Autodesk Fusion 360 part; units mm, degrees
(part 22 of 28)
  line L283 (90.6748, 11.0958, -1.4859) -> (90.5767, 11.092, -1.4859)
  line L284 (90.5767, 11.092, -1.4859) -> (90.0767, 11.092, -1.4859)
  line L285 (90.0767, 11.092, -1.4859) -> (89.9787, 11.0958, -1.4859)
  line L286 (89.9787, 11.0958, -1.4859) -> (89.7849, 11.1265, -1.4859)
  line L287 (89.7849, 11.1265, -1.4859) -> (89.5984, 11.1871, -1.4859)
  line L288 (89.5984, 11.1871, -1.4859) -> (89.4236, 11.2762, -1.4859)
  line L289 (89.4236, 11.2762, -1.4859) -> (89.2649, 11.3915, -1.4859)
  line L290 (89.2649, 11.3915, -1.4859) -> (89.1262, 11.5301, -1.4859)
  line L291 (89.1262, 11.5301, -1.4859) -> (89.0109, 11.6888, -1.4859)
  line L292 (89.0109, 11.6888, -1.4859) -> (88.9219, 11.8636, -1.4859)
  line L293 (88.9219, 11.8636, -1.4859) -> (88.8613, 12.0501, -1.4859)
  line L294 (88.8613, 12.0501, -1.4859) -> (88.8306, 12.2439, -1.4859)
  line L295 (88.8306, 12.2439, -1.4859) -> (88.8306, 12.44, -1.4859)
  line L296 (88.8306, 12.44, -1.4859) -> (88.8613, 12.6338, -1.4859)
  line L297 (88.8613, 12.6338, -1.4859) -> (88.9219, 12.8203, -1.4859)
  line L298 (88.9219, 12.8203, -1.4859) -> (89.0109, 12.9951, -1.4859)
  line L299 (89.0109, 12.9951, -1.4859) -> (89.1262, 13.1538, -1.4859)
  line L300 (89.1262, 13.1538, -1.4859) -> (89.2649, 13.2925, -1.4859)
  line L301 (89.2649, 13.2925, -1.4859) -> (89.4236, 13.4078, -1.4859)
  line L302 (89.4236, 13.4078, -1.4859) -> (89.5984, 13.4968, -1.4859)
  line L303 (89.5984, 13.4968, -1.4859) -> (89.7849, 13.5574, -1.4859)
  line L304 (89.7849, 13.5574, -1.4859) -> (89.9787, 13.5881, -1.4859)
  line L305 (89.9787, 13.5881, -1.4859) -> (90.0767, 13.592, -1.4859)
  line L306 (90.0767, 13.592, -1.4859) -> (90.5767, 13.592, -1.4859)
  line L307 (90.5767, 13.592, -1.4859) -> (90.6748, 13.5881, -1.4859)
  line L308 (98.2948, 13.5881, -1.4859) -> (98.4885, 13.5574, -1.4859)
  line L309 (98.4885, 13.5574, -1.4859) -> (98.6751, 13.4968, -1.4859)
  line L310 (98.6751, 13.4968, -1.4859) -> (98.8499, 13.4078, -1.4859)
  line L311 (98.8499, 13.4078, -1.4859) -> (99.0085, 13.2925, -1.4859)
  line L312 (99.0085, 13.2925, -1.4859) -> (99.1472, 13.1538, -1.4859)
  line L313 (99.1472, 13.1538, -1.4859) -> (99.2625, 12.9951, -1.4859)
  line L314 (99.2625, 12.9951, -1.4859) -> (99.3516, 12.8203, -1.4859)
  line L315 (99.3516, 12.8203, -1.4859) -> (99.4122, 12.6338, -1.4859)
  line L316 (99.4122, 12.6338, -1.4859) -> (99.4429, 12.44, -1.4859)
  line L317 (99.4429, 12.44, -1.4859) -> (99.4429, 12.2439, -1.4859)
  line L318 (99.4429, 12.2439, -1.4859) -> (99.4122, 12.0501, -1.4859)
  line L319 (99.4122, 12.0501, -1.4859) -> (99.3516, 11.8636, -1.4859)
  line L320 (99.3516, 11.8636, -1.4859) -> (99.2625, 11.6888, -1.4859)
  line L321 (99.2625, 11.6888, -1.4859) -> (99.1472, 11.5301, -1.4859)
  line L322 (99.1472, 11.5301, -1.4859) -> (99.0086, 11.3914, -1.4859)
  line L323 (99.0086, 11.3914, -1.4859) -> (98.8499, 11.2762, -1.4859)
  line L324 (98.8499, 11.2762, -1.4859) -> (98.6751, 11.1871, -1.4859)
  line L325 (98.6751, 11.1871, -1.4859) -> (98.4885, 11.1265, -1.4859)
  line L326 (98.4885, 11.1265, -1.4859) -> (98.2948, 11.0958, -1.4859)
  line L327 (98.2948, 11.0958, -1.4859) -> (98.1967, 11.092, -1.4859)
  line L328 (98.1967, 11.092, -1.4859) -> (97.6967, 11.092, -1.4859)
  line L329 (97.6967, 11.092, -1.4859) -> (97.5987, 11.0958, -1.4859)
  line L330 (97.5987, 11.0958, -1.4859) -> (97.4049, 11.1265, -1.4859)
  line L331 (97.4049, 11.1265, -1.4859) -> (97.2184, 11.1871, -1.4859)
  line L332 (97.2184, 11.1871, -1.4859) -> (97.0436, 11.2762, -1.4859)
  line L333 (97.0436, 11.2762, -1.4859) -> (96.8849, 11.3915, -1.4859)
  line L334 (96.8849, 11.3915, -1.4859) -> (96.7462, 11.5301, -1.4859)
  line L335 (96.7462, 11.5301, -1.4859) -> (96.6309, 11.6888, -1.4859)
  line L336 (96.6309, 11.6888, -1.4859) -> (96.5419, 11.8636, -1.4859)
  line L337 (96.5419, 11.8636, -1.4859) -> (96.4813, 12.0501, -1.4859)
  line L338 (96.4813, 12.0501, -1.4859) -> (96.4506, 12.2439, -1.4859)
  line L339 (96.4506, 12.2439, -1.4859) -> (96.4506, 12.44, -1.4859)
  line L340 (96.4506, 12.44, -1.4859) -> (96.4813, 12.6338, -1.4859)
  line L341 (96.4813, 12.6338, -1.4859) -> (96.5419, 12.8203, -1.4859)
  line L342 (96.5419, 12.8203, -1.4859) -> (96.6309, 12.9951, -1.4859)
  line L343 (96.6309, 12.9951, -1.4859) -> (96.7462, 13.1538, -1.4859)
  line L344 (96.7462, 13.1538, -1.4859) -> (96.8849, 13.2925, -1.4859)
  line L345 (96.8849, 13.2925, -1.4859) -> (97.0436, 13.4078, -1.4859)
  line L346 (97.0436, 13.4078, -1.4859) -> (97.2184, 13.4968, -1.4859)
  line L347 (97.2184, 13.4968, -1.4859) -> (97.4049, 13.5574, -1.4859)
  line L348 (97.4049, 13.5574, -1.4859) -> (97.5987, 13.5881, -1.4859)
  line L349 (97.5987, 13.5881, -1.4859) -> (97.6967, 13.592, -1.4859)
  line L350 (97.6967, 13.592, -1.4859) -> (98.1967, 13.592, -1.4859)
  line L351 (98.1967, 13.592, -1.4859) -> (98.2948, 13.5881, -1.4859)
  line L352 (43.8133, 16.6136, -1.4859) -> (44.0056, 16.5753, -1.4859)
  line L353 (44.0056, 16.5753, -1.4859) -> (44.1867, 16.5003, -1.4859)
  line L354 (44.1867, 16.5003, -1.4859) -> (44.3497, 16.3914, -1.4859)
  line L355 (44.3497, 16.3914, -1.4859) -> (44.4883, 16.2528, -1.4859)
  line L356 (44.4883, 16.2528, -1.4859) -> (44.5972, 16.0898, -1.4859)
  line L357 (44.5972, 16.0898, -1.4859) -> (44.6722, 15.9087, -1.4859)
  line L358 (44.6722, 15.9087, -1.4859) -> (44.7105, 15.7164, -1.4859)
  line L359 (44.7105, 15.7164, -1.4859) -> (44.7105, 15.5204, -1.4859)
  line L360 (44.7105, 15.5204, -1.4859) -> (44.6722, 15.3281, -1.4859)
  line L361 (44.6722, 15.3281, -1.4859) -> (44.5972, 15.147, -1.4859)
  line L362 (44.5972, 15.147, -1.4859) -> (44.4883, 14.984, -1.4859)
  line L363 (44.4883, 14.984, -1.4859) -> (44.3497, 14.8454, -1.4859)
  line L364 (44.3497, 14.8454, -1.4859) -> (44.1867, 14.7365, -1.4859)
  line L365 (44.1867, 14.7365, -1.4859) -> (44.0056, 14.6615, -1.4859)
  line L366 (44.0056, 14.6615, -1.4859) -> (43.8133, 14.6232, -1.4859)
  line L367 (43.8133, 14.6232, -1.4859) -> (43.7153, 14.6184, -1.4859)
  line L368 (43.7153, 14.6184, -1.4859) -> (42.5153, 14.6184, -1.4859)
  line L369 (42.5153, 14.6184, -1.4859) -> (42.4173, 14.6232, -1.4859)
  line L370 (42.4173, 14.6232, -1.4859) -> (42.225, 14.6615, -1.4859)
  line L371 (42.225, 14.6615, -1.4859) -> (42.0439, 14.7365, -1.4859)
  line L372 (42.0439, 14.7365, -1.4859) -> (41.8809, 14.8454, -1.4859)
  line L373 (41.8809, 14.8454, -1.4859) -> (41.7423, 14.984, -1.4859)
  line L374 (41.7423, 14.984, -1.4859) -> (41.6334, 15.147, -1.4859)
  line L375 (41.6334, 15.147, -1.4859) -> (41.5583, 15.3281, -1.4859)
  line L376 (41.5583, 15.3281, -1.4859) -> (41.5201, 15.5204, -1.4859)
  line L377 (41.5201, 15.5204, -1.4859) -> (41.5201, 15.7164, -1.4859)
  line L378 (41.5201, 15.7164, -1.4859) -> (41.5583, 15.9087, -1.4859)
  line L379 (41.5583, 15.9087, -1.4859) -> (41.6334, 16.0898, -1.4859)
  line L380 (41.6334, 16.0898, -1.4859) -> (41.7423, 16.2528, -1.4859)
  line L381 (41.7423, 16.2528, -1.4859) -> (41.8809, 16.3914, -1.4859)
  line L382 (41.8809, 16.3914, -1.4859) -> (42.0439, 16.5003, -1.4859)
  line L383 (42.0439, 16.5003, -1.4859) -> (42.225, 16.5753, -1.4859)
  line L384 (42.225, 16.5753, -1.4859) -> (42.4173, 16.6136, -1.4859)
  line L385 (42.4173, 16.6136, -1.4859) -> (42.5153, 16.6184, -1.4859)
  line L386 (42.5153, 16.6184, -1.4859) -> (43.7153, 16.6184, -1.4859)
  line L387 (43.7153, 16.6184, -1.4859) -> (43.8133, 16.6136, -1.4859)
  line L388 (104.7733, 16.6136, -1.4859) -> (104.9656, 16.5753, -1.4859)
  line L389 (104.9656, 16.5753, -1.4859) -> (105.1467, 16.5003, -1.4859)
  line L390 (105.1467, 16.5003, -1.4859) -> (105.3097, 16.3914, -1.4859)
  line L391 (105.3097, 16.3914, -1.4859) -> (105.4483, 16.2528, -1.4859)
  line L392 (105.4483, 16.2528, -1.4859) -> (105.5572, 16.0898, -1.4859)
  line L393 (105.5572, 16.0898, -1.4859) -> (105.6322, 15.9087, -1.4859)
  line L394 (105.6322, 15.9087, -1.4859) -> (105.6705, 15.7164, -1.4859)
  line L395 (105.6705, 15.7164, -1.4859) -> (105.6705, 15.5204, -1.4859)
  line L396 (105.6705, 15.5204, -1.4859) -> (105.6322, 15.3281, -1.4859)
  line L397 (105.6322, 15.3281, -1.4859) -> (105.5572, 15.147, -1.4859)
  line L398 (105.5572, 15.147, -1.4859) -> (105.4483, 14.984, -1.4859)
  line L399 (105.4483, 14.984, -1.4859) -> (105.3097, 14.8454, -1.4859)
  line L400 (105.3097, 14.8454, -1.4859) -> (105.1467, 14.7365, -1.4859)
  line L401 (105.1467, 14.7365, -1.4859) -> (104.9656, 14.6615, -1.4859)
  line L402 (104.9656, 14.6615, -1.4859) -> (104.7733, 14.6232, -1.4859)
  line L403 (104.7733, 14.6232, -1.4859) -> (104.6753, 14.6184, -1.4859)
  line L404 (104.6753, 14.6184, -1.4859) -> (103.4753, 14.6184, -1.4859)
  line L405 (103.4753, 14.6184, -1.4859) -> (103.3773, 14.6232, -1.4859)
  line L406 (103.3773, 14.6232, -1.4859) -> (103.185, 14.6615, -1.4859)
  line L407 (103.185, 14.6615, -1.4859) -> (103.0039, 14.7365, -1.4859)
  line L408 (103.0039, 14.7365, -1.4859) -> (102.8409, 14.8454, -1.4859)
  line L409 (102.8409, 14.8454, -1.4859) -> (102.7023, 14.984, -1.4859)
  line L410 (102.7023, 14.984, -1.4859) -> (102.5934, 15.147, -1.4859)
  line L411 (102.5934, 15.147, -1.4859) -> (102.5183, 15.3281, -1.4859)
  line L412 (102.5183, 15.3281, -1.4859) -> (102.4801, 15.5204, -1.4859)
  line L413 (102.4801, 15.5204, -1.4859) -> (102.4801, 15.7164, -1.4859)
  line L414 (102.4801, 15.7164, -1.4859) -> (102.5183, 15.9087, -1.4859)
  line L415 (102.5183, 15.9087, -1.4859) -> (102.5934, 16.0898, -1.4859)
  line L416 (102.5934, 16.0898, -1.4859) -> (102.7023, 16.2528, -1.4859)
  line L417 (102.7023, 16.2528, -1.4859) -> (102.8409, 16.3914, -1.4859)
  line L418 (102.8409, 16.3914, -1.4859) -> (103.0039, 16.5003, -1.4859)
  line L419 (103.0039, 16.5003, -1.4859) -> (103.185, 16.5753, -1.4859)
  line L420 (103.185, 16.5753, -1.4859) -> (103.3773, 16.6136, -1.4859)
  line L421 (103.3773, 16.6136, -1.4859) -> (103.4753, 16.6184, -1.4859)
  line L422 (103.4753, 16.6184, -1.4859) -> (104.6753, 16.6184, -1.4859)
  line L423 (104.6753, 16.6184, -1.4859) -> (104.7733, 16.6136, -1.4859)
  line L424 (21.9861, 18.9762, -1.4859) -> (22.176, 18.9462, -1.4859)
  line L425 (22.176, 18.9462, -1.4859) -> (22.3588, 18.8868, -1.4859)
  line L426 (22.3588, 18.8868, -1.4859) -> (22.5301, 18.7995, -1.4859)
  line L427 (22.5301, 18.7995, -1.4859) -> (22.6856, 18.6865, -1.4859)
  line L428 (22.6856, 18.6865, -1.4859) -> (22.8215, 18.5506, -1.4859)
  line L429 (22.8215, 18.5506, -1.4859) -> (22.9345, 18.3951, -1.4859)
  line L430 (22.9345, 18.3951, -1.4859) -> (23.0218, 18.2238, -1.4859)
  line L431 (23.0218, 18.2238, -1.4859) -> (23.0812, 18.041, -1.4859)
  line L432 (23.0812, 18.041, -1.4859) -> (23.1112, 17.8511, -1.4859)
  line L433 (23.1112, 17.8511, -1.4859) -> (23.1112, 17.6589, -1.4859)
  line L434 (23.1112, 17.6589, -1.4859) -> (23.0812, 17.469, -1.4859)
  line L435 (23.0812, 17.469, -1.4859) -> (23.0218, 17.2862, -1.4859)
  line L436 (23.0218, 17.2862, -1.4859) -> (22.9345, 17.1149, -1.4859)
  line L437 (22.9345, 17.1149, -1.4859) -> (22.8215, 16.9594, -1.4859)
  line L438 (22.8215, 16.9594, -1.4859) -> (22.6856, 16.8235, -1.4859)
  line L439 (22.6856, 16.8235, -1.4859) -> (22.5301, 16.7105, -1.4859)
  line L440 (22.5301, 16.7105, -1.4859) -> (22.3588, 16.6232, -1.4859)
  line L441 (22.3588, 16.6232, -1.4859) -> (22.176, 16.5638, -1.4859)
  line L442 (22.176, 16.5638, -1.4859) -> (21.9861, 16.5338, -1.4859)
  line L443 (21.9861, 16.5338, -1.4859) -> (21.89, 16.53, -1.4859)
  line L444 (21.89, 16.53, -1.4859) -> (21.34, 16.53, -1.4859)
  line L445 (21.34, 16.53, -1.4859) -> (21.2439, 16.5338, -1.4859)
  line L446 (21.2439, 16.5338, -1.4859) -> (21.054, 16.5638, -1.4859)
  line L447 (21.054, 16.5638, -1.4859) -> (20.8712, 16.6232, -1.4859)
  line L448 (20.8712, 16.6232, -1.4859) -> (20.6999, 16.7105, -1.4859)
  line L449 (20.6999, 16.7105, -1.4859) -> (20.5444, 16.8235, -1.4859)
  line L450 (20.5444, 16.8235, -1.4859) -> (20.4085, 16.9594, -1.4859)
  line L451 (20.4085, 16.9594, -1.4859) -> (20.2955, 17.1149, -1.4859)
  line L452 (20.2955, 17.1149, -1.4859) -> (20.2082, 17.2862, -1.4859)
  line L453 (20.2082, 17.2862, -1.4859) -> (20.1488, 17.469, -1.4859)
  line L454 (20.1488, 17.469, -1.4859) -> (20.1188, 17.6589, -1.4859)
  line L455 (20.1188, 17.6589, -1.4859) -> (20.1188, 17.8511, -1.4859)
  line L456 (20.1188, 17.8511, -1.4859) -> (20.1488, 18.041, -1.4859)
  line L457 (20.1488, 18.041, -1.4859) -> (20.2082, 18.2238, -1.4859)
  line L458 (20.2082, 18.2238, -1.4859) -> (20.2955, 18.3951, -1.4859)
  line L459 (20.2955, 18.3951, -1.4859) -> (20.4085, 18.5506, -1.4859)
  line L460 (20.4085, 18.5506, -1.4859) -> (20.5444, 18.6865, -1.4859)
  line L461 (20.5444, 18.6865, -1.4859) -> (20.6999, 18.7995, -1.4859)
  line L462 (20.6999, 18.7995, -1.4859) -> (20.8712, 18.8868, -1.4859)
  line L463 (20.8712, 18.8868, -1.4859) -> (21.054, 18.9462, -1.4859)
  line L464 (21.054, 18.9462, -1.4859) -> (21.2439, 18.9762, -1.4859)
  line L465 (21.2439, 18.9762, -1.4859) -> (21.34, 18.98, -1.4859)
  line L466 (21.34, 18.98, -1.4859) -> (21.89, 18.98, -1.4859)
  line L467 (21.89, 18.98, -1.4859) -> (21.9861, 18.9762, -1.4859)
  line L468 (82.9461, 18.9762, -1.4859) -> (83.136, 18.9462, -1.4859)
  line L469 (83.136, 18.9462, -1.4859) -> (83.3188, 18.8868, -1.4859)
  line L470 (83.3188, 18.8868, -1.4859) -> (83.4901, 18.7995, -1.4859)
  line L471 (83.4901, 18.7995, -1.4859) -> (83.6456, 18.6865, -1.4859)
  line L472 (83.6456, 18.6865, -1.4859) -> (83.7815, 18.5506, -1.4859)
  line L473 (83.7815, 18.5506, -1.4859) -> (83.8945, 18.3951, -1.4859)
  line L474 (83.8945, 18.3951, -1.4859) -> (83.9818, 18.2238, -1.4859)
  line L475 (83.9818, 18.2238, -1.4859) -> (84.0412, 18.041, -1.4859)
  line L476 (84.0412, 18.041, -1.4859) -> (84.0712, 17.8511, -1.4859)
  line L477 (84.0712, 17.8511, -1.4859) -> (84.0712, 17.6589, -1.4859)
  line L478 (84.0712, 17.6589, -1.4859) -> (84.0412, 17.469, -1.4859)
  line L479 (84.0412, 17.469, -1.4859) -> (83.9818, 17.2862, -1.4859)
  line L480 (83.9818, 17.2862, -1.4859) -> (83.8945, 17.1149, -1.4859)
  line L481 (83.8945, 17.1149, -1.4859) -> (83.7815, 16.9594, -1.4859)
  line L482 (83.7815, 16.9594, -1.4859) -> (83.6456, 16.8235, -1.4859)
  line L483 (83.6456, 16.8235, -1.4859) -> (83.4901, 16.7105, -1.4859)
  line L484 (83.4901, 16.7105, -1.4859) -> (83.3188, 16.6232, -1.4859)
  line L485 (83.3188, 16.6232, -1.4859) -> (83.136, 16.5638, -1.4859)
  line L486 (83.136, 16.5638, -1.4859) -> (82.9461, 16.5338, -1.4859)
  line L487 (82.9461, 16.5338, -1.4859) -> (82.85, 16.53, -1.4859)
  line L488 (82.85, 16.53, -1.4859) -> (82.3, 16.53, -1.4859)
  line L489 (82.3, 16.53, -1.4859) -> (82.2039, 16.5338, -1.4859)
  line L490 (82.2039, 16.5338, -1.4859) -> (82.014, 16.5638, -1.4859)
  line L491 (82.014, 16.5638, -1.4859) -> (81.8312, 16.6232, -1.4859)
  line L492 (81.8312, 16.6232, -1.4859) -> (81.6599, 16.7105, -1.4859)
  line L493 (81.6599, 16.7105, -1.4859) -> (81.5044, 16.8235, -1.4859)
  line L494 (81.5044, 16.8235, -1.4859) -> (81.3685, 16.9594, -1.4859)
  line L495 (81.3685, 16.9594, -1.4859) -> (81.2555, 17.1149, -1.4859)
  line L496 (81.2555, 17.1149, -1.4859) -> (81.1682, 17.2862, -1.4859)
  line L497 (81.1682, 17.2862, -1.4859) -> (81.1088, 17.469, -1.4859)
  line L498 (81.1088, 17.469, -1.4859) -> (81.0788, 17.6589, -1.4859)
  line L499 (81.0788, 17.6589, -1.4859) -> (81.0788, 17.8511, -1.4859)
  line L500 (81.0788, 17.8511, -1.4859) -> (81.1088, 18.041, -1.4859)
  line L501 (81.1088, 18.041, -1.4859) -> (81.1682, 18.2238, -1.4859)
  line L502 (81.1682, 18.2238, -1.4859) -> (81.2555, 18.3951, -1.4859)
  line L503 (81.2555, 18.3951, -1.4859) -> (81.3685, 18.5506, -1.4859)
  line L504 (81.3685, 18.5506, -1.4859) -> (81.5044, 18.6865, -1.4859)
  line L505 (81.5044, 18.6865, -1.4859) -> (81.6599, 18.7995, -1.4859)
  line L506 (81.6599, 18.7995, -1.4859) -> (81.8312, 18.8868, -1.4859)
  line L507 (81.8312, 18.8868, -1.4859) -> (82.014, 18.9462, -1.4859)
  line L508 (82.014, 18.9462, -1.4859) -> (82.2039, 18.9762, -1.4859)
  line L509 (82.2039, 18.9762, -1.4859) -> (82.3, 18.98, -1.4859)
  line L510 (82.3, 18.98, -1.4859) -> (82.85, 18.98, -1.4859)
  line L511 (82.85, 18.98, -1.4859) -> (82.9461, 18.9762, -1.4859)
  line L512 (43.8133, 19.3436, -1.4859) -> (44.0056, 19.3053, -1.4859)
  line L513 (44.0056, 19.3053, -1.4859) -> (44.1867, 19.2303, -1.4859)
  line L514 (44.1867, 19.2303, -1.4859) -> (44.3497, 19.1214, -1.4859)
  line L515 (44.3497, 19.1214, -1.4859) -> (44.4883, 18.9828, -1.4859)
  line L516 (44.4883, 18.9828, -1.4859) -> (44.5972, 18.8198, -1.4859)
  line L517 (44.5972, 18.8198, -1.4859) -> (44.6722, 18.6387, -1.4859)
  line L518 (44.6722, 18.6387, -1.4859) -> (44.7105, 18.4464, -1.4859)
  line L519 (44.7105, 18.4464, -1.4859) -> (44.7105, 18.2504, -1.4859)
  line L520 (44.7105, 18.2504, -1.4859) -> (44.6722, 18.0581, -1.4859)
  line L521 (44.6722, 18.0581, -1.4859) -> (44.5972, 17.877, -1.4859)
  line L522 (44.5972, 17.877, -1.4859) -> (44.4883, 17.714, -1.4859)
  line L523 (44.4883, 17.714, -1.4859) -> (44.3497, 17.5754, -1.4859)
  line L524 (44.3497, 17.5754, -1.4859) -> (44.1867, 17.4665, -1.4859)
  line L525 (44.1867, 17.4665, -1.4859) -> (44.0056, 17.3915, -1.4859)
  line L526 (44.0056, 17.3915, -1.4859) -> (43.8133, 17.3532, -1.4859)
  line L527 (43.8133, 17.3532, -1.4859) -> (43.7153, 17.3484, -1.4859)
  line L528 (43.7153, 17.3484, -1.4859) -> (42.5153, 17.3484, -1.4859)
  line L529 (42.5153, 17.3484, -1.4859) -> (42.4173, 17.3532, -1.4859)
  line L530 (42.4173, 17.3532, -1.4859) -> (42.225, 17.3915, -1.4859)
  line L531 (42.225, 17.3915, -1.4859) -> (42.0439, 17.4665, -1.4859)
  line L532 (42.0439, 17.4665, -1.4859) -> (41.8809, 17.5754, -1.4859)
  line L533 (41.8809, 17.5754, -1.4859) -> (41.7423, 17.714, -1.4859)
  line L534 (41.7423, 17.714, -1.4859) -> (41.6334, 17.877, -1.4859)
  line L535 (41.6334, 17.877, -1.4859) -> (41.5583, 18.0581, -1.4859)
  line L536 (41.5583, 18.0581, -1.4859) -> (41.5201, 18.2504, -1.4859)
  line L537 (41.5201, 18.2504, -1.4859) -> (41.5201, 18.4464, -1.4859)
  line L538 (41.5201, 18.4464, -1.4859) -> (41.5583, 18.6387, -1.4859)
  line L539 (41.5583, 18.6387, -1.4859) -> (41.6334, 18.8198, -1.4859)
  line L540 (41.6334, 18.8198, -1.4859) -> (41.7423, 18.9828, -1.4859)
  line L541 (41.7423, 18.9828, -1.4859) -> (41.8809, 19.1214, -1.4859)
  line L542 (41.8809, 19.1214, -1.4859) -> (42.0439, 19.2303, -1.4859)
  line L543 (42.0439, 19.2303, -1.4859) -> (42.225, 19.3053, -1.4859)
  line L544 (42.225, 19.3053, -1.4859) -> (42.4173, 19.3436, -1.4859)
  line L545 (42.4173, 19.3436, -1.4859) -> (42.5153, 19.3484, -1.4859)
  line L546 (42.5153, 19.3484, -1.4859) -> (43.7153, 19.3484, -1.4859)
  line L547 (43.7153, 19.3484, -1.4859) -> (43.8133, 19.3436, -1.4859)
  line L548 (104.7733, 19.3436, -1.4859) -> (104.9656, 19.3053, -1.4859)
  line L549 (104.9656, 19.3053, -1.4859) -> (105.1467, 19.2303, -1.4859)
  line L550 (105.1467, 19.2303, -1.4859) -> (105.3097, 19.1214, -1.4859)
  line L551 (105.3097, 19.1214, -1.4859) -> (105.4483, 18.9828, -1.4859)
  line L552 (105.4483, 18.9828, -1.4859) -> (105.5572, 18.8198, -1.4859)
  line L553 (105.5572, 18.8198, -1.4859) -> (105.6322, 18.6387, -1.4859)
  line L554 (105.6322, 18.6387, -1.4859) -> (105.6705, 18.4464, -1.4859)
  line L555 (105.6705, 18.4464, -1.4859) -> (105.6705, 18.2504, -1.4859)
  line L556 (105.6705, 18.2504, -1.4859) -> (105.6322, 18.0581, -1.4859)
  line L557 (105.6322, 18.0581, -1.4859) -> (105.5572, 17.877, -1.4859)
  line L558 (105.5572, 17.877, -1.4859) -> (105.4483, 17.714, -1.4859)
  line L559 (105.4483, 17.714, -1.4859) -> (105.3097, 17.5754, -1.4859)
  line L560 (105.3097, 17.5754, -1.4859) -> (105.1467, 17.4665, -1.4859)
  line L561 (105.1467, 17.4665, -1.4859) -> (104.9656, 17.3915, -1.4859)
  line L562 (104.9656, 17.3915, -1.4859) -> (104.7733, 17.3532, -1.4859)
  line L563 (104.7733, 17.3532, -1.4859) -> (104.6753, 17.3484, -1.4859)
  line L564 (104.6753, 17.3484, -1.4859) -> (103.4753, 17.3484, -1.4859)
  line L565 (103.4753, 17.3484, -1.4859) -> (103.3773, 17.3532, -1.4859)
  line L566 (103.3773, 17.3532, -1.4859) -> (103.185, 17.3915, -1.4859)
  line L567 (103.185, 17.3915, -1.4859) -> (103.0039, 17.4665, -1.4859)
  line L568 (103.0039, 17.4665, -1.4859) -> (102.8409, 17.5754, -1.4859)
  line L569 (102.8409, 17.5754, -1.4859) -> (102.7023, 17.714, -1.4859)
  line L570 (102.7023, 17.714, -1.4859) -> (102.5934, 17.877, -1.4859)
  line L571 (102.5934, 17.877, -1.4859) -> (102.5183, 18.0581, -1.4859)
  line L572 (102.5183, 18.0581, -1.4859) -> (102.4801, 18.2504, -1.4859)
  line L573 (102.4801, 18.2504, -1.4859) -> (102.4801, 18.4464, -1.4859)
  line L574 (102.4801, 18.4464, -1.4859) -> (102.5183, 18.6387, -1.4859)
  line L575 (102.5183, 18.6387, -1.4859) -> (102.5934, 18.8198, -1.4859)
  line L576 (102.5934, 18.8198, -1.4859) -> (102.7023, 18.9828, -1.4859)
  line L577 (102.7023, 18.9828, -1.4859) -> (102.8409, 19.1214, -1.4859)
  line L578 (102.8409, 19.1214, -1.4859) -> (103.0039, 19.2303, -1.4859)
  line L579 (103.0039, 19.2303, -1.4859) -> (103.185, 19.3053, -1.4859)
  line L580 (103.185, 19.3053, -1.4859) -> (103.3773, 19.3436, -1.4859)
  line L581 (103.3773, 19.3436, -1.4859) -> (103.4753, 19.3484, -1.4859)
  line L582 (103.4753, 19.3484, -1.4859) -> (104.6753, 19.3484, -1.4859)
  line L583 (104.6753, 19.3484, -1.4859) -> (104.7733, 19.3436, -1.4859)
  line L584 (22.8414, 21.4641, -1.4859) -> (22.9546, 21.4087, -1.4859)
  line L585 (22.9546, 21.4087, -1.4859) -> (23.0437, 21.3196, -1.4859)
  line L586 (23.0437, 21.3196, -1.4859) -> (23.0991, 21.2064, -1.4859)
  line L587 (23.0991, 21.2064, -1.4859) -> (23.115, 21.0972, -1.4859)
  line L588 (23.115, 21.0972, -1.4859) -> (23.115, 19.4128, -1.4859)
  line L589 (23.115, 19.4128, -1.4859) -> (23.0991, 19.3036, -1.4859)
  line L590 (23.0991, 19.3036, -1.4859) -> (23.0437, 19.1904, -1.4859)
  line L591 (23.0437, 19.1904, -1.4859) -> (22.9546, 19.1013, -1.4859)
  line L592 (22.9546, 19.1013, -1.4859) -> (22.8414, 19.0459, -1.4859)
  line L593 (22.8414, 19.0459, -1.4859) -> (22.7322, 19.03, -1.4859)
  line L594 (22.7322, 19.03, -1.4859) -> (20.4978, 19.03, -1.4859)
  line L595 (20.4978, 19.03, -1.4859) -> (20.3886, 19.0459, -1.4859)
  line L596 (20.3886, 19.0459, -1.4859) -> (20.2754, 19.1013, -1.4859)
  line L597 (20.2754, 19.1013, -1.4859) -> (20.1863, 19.1904, -1.4859)
  line L598 (20.1863, 19.1904, -1.4859) -> (20.1309, 19.3036, -1.4859)
  line L599 (20.1309, 19.3036, -1.4859) -> (20.115, 19.4128, -1.4859)
  line L600 (20.115, 19.4128, -1.4859) -> (20.115, 21.0972, -1.4859)
  line L601 (20.115, 21.0972, -1.4859) -> (20.1309, 21.2064, -1.4859)
  line L602 (20.1309, 21.2064, -1.4859) -> (20.1863, 21.3196, -1.4859)
  line L603 (20.1863, 21.3196, -1.4859) -> (20.2754, 21.4087, -1.4859)
  line L604 (20.2754, 21.4087, -1.4859) -> (20.3886, 21.4641, -1.4859)
  line L605 (20.3886, 21.4641, -1.4859) -> (20.4978, 21.48, -1.4859)
  line L606 (20.4978, 21.48, -1.4859) -> (22.7322, 21.48, -1.4859)
  line L607 (22.7322, 21.48, -1.4859) -> (22.8414, 21.4641, -1.4859)
  line L608 (83.8014, 21.4641, -1.4859) -> (83.9146, 21.4087, -1.4859)
  line L609 (83.9146, 21.4087, -1.4859) -> (84.0037, 21.3196, -1.4859)
  line L610 (84.0037, 21.3196, -1.4859) -> (84.0591, 21.2064, -1.4859)
  line L611 (84.0591, 21.2064, -1.4859) -> (84.075, 21.0972, -1.4859)
  line L612 (84.075, 21.0972, -1.4859) -> (84.075, 19.4128, -1.4859)
  line L613 (84.075, 19.4128, -1.4859) -> (84.0591, 19.3036, -1.4859)
  line L614 (84.0591, 19.3036, -1.4859) -> (84.0037, 19.1904, -1.4859)
  line L615 (84.0037, 19.1904, -1.4859) -> (83.9146, 19.1013, -1.4859)
  line L616 (83.9146, 19.1013, -1.4859) -> (83.8014, 19.0459, -1.4859)
  line L617 (83.8014, 19.0459, -1.4859) -> (83.6922, 19.03, -1.4859)
  line L618 (83.6922, 19.03, -1.4859) -> (81.4578, 19.03, -1.4859)
  line L619 (81.4578, 19.03, -1.4859) -> (81.3486, 19.0459, -1.4859)
  line L620 (81.3486, 19.0459, -1.4859) -> (81.2354, 19.1013, -1.4859)
  line L621 (81.2354, 19.1013, -1.4859) -> (81.1463, 19.1904, -1.4859)
  line L622 (81.1463, 19.1904, -1.4859) -> (81.0909, 19.3036, -1.4859)
  line L623 (81.0909, 19.3036, -1.4859) -> (81.075, 19.4128, -1.4859)
  line L624 (81.075, 19.4128, -1.4859) -> (81.075, 21.0972, -1.4859)
  line L625 (81.075, 21.0972, -1.4859) -> (81.0909, 21.2064, -1.4859)
  line L626 (81.0909, 21.2064, -1.4859) -> (81.1463, 21.3196, -1.4859)
  line L627 (81.1463, 21.3196, -1.4859) -> (81.2354, 21.4087, -1.4859)
  line L628 (81.2354, 21.4087, -1.4859) -> (81.3486, 21.4641, -1.4859)
  line L629 (81.3486, 21.4641, -1.4859) -> (81.4578, 21.48, -1.4859)
  line L630 (81.4578, 21.48, -1.4859) -> (83.6922, 21.48, -1.4859)
  line L631 (83.6922, 21.48, -1.4859) -> (83.8014, 21.4641, -1.4859)
  line L632 (32.7386, 22.7176, -1.4859) -> (32.9251, 22.657, -1.4859)
  line L633 (32.9251, 22.657, -1.4859) -> (33.0999, 22.5679, -1.4859)
  line L634 (33.0999, 22.5679, -1.4859) -> (33.2586, 22.4526, -1.4859)
  line L635 (33.2586, 22.4526, -1.4859) -> (33.3973, 22.3139, -1.4859)
  line L636 (33.3973, 22.3139, -1.4859) -> (33.5126, 22.1552, -1.4859)
  line L637 (33.5126, 22.1552, -1.4859) -> (33.6016, 21.9805, -1.4859)
  line L638 (33.6016, 21.9805, -1.4859) -> (33.6622, 21.7939, -1.4859)
  line L639 (33.6622, 21.7939, -1.4859) -> (33.6929, 21.6002, -1.4859)
  line L640 (33.6929, 21.6002, -1.4859) -> (33.6968, 21.5021, -1.4859)
  line L641 (33.6968, 21.5021, -1.4859) -> (33.6968, 21.0021, -1.4859)
  line L642 (33.6968, 21.0021, -1.4859) -> (33.6929, 20.904, -1.4859)
  line L643 (33.6929, 20.904, -1.4859) -> (33.6622, 20.7103, -1.4859)
  line L644 (33.6622, 20.7103, -1.4859) -> (33.6016, 20.5238, -1.4859)
  line L645 (33.6016, 20.5238, -1.4859) -> (33.5126, 20.349, -1.4859)
  line L646 (33.5126, 20.349, -1.4859) -> (33.3973, 20.1903, -1.4859)
  line L647 (33.3973, 20.1903, -1.4859) -> (33.2586, 20.0516, -1.4859)
  line L648 (33.2586, 20.0516, -1.4859) -> (33.0999, 19.9363, -1.4859)
  line L649 (33.0999, 19.9363, -1.4859) -> (32.9251, 19.8473, -1.4859)
  line L650 (32.9251, 19.8473, -1.4859) -> (32.7386, 19.7866, -1.4859)
  line L651 (32.7386, 19.7866, -1.4859) -> (32.5448, 19.756, -1.4859)
  line L652 (32.5448, 19.756, -1.4859) -> (32.3487, 19.756, -1.4859)
  line L653 (32.3487, 19.756, -1.4859) -> (32.155, 19.7866, -1.4859)
  line L654 (32.155, 19.7866, -1.4859) -> (31.9684, 19.8473, -1.4859)
  line L655 (31.9684, 19.8473, -1.4859) -> (31.7936, 19.9363, -1.4859)
  line L656 (31.7936, 19.9363, -1.4859) -> (31.635, 20.0516, -1.4859)
  line L657 (31.635, 20.0516, -1.4859) -> (31.4963, 20.1903, -1.4859)
  line L658 (31.4963, 20.1903, -1.4859) -> (31.381, 20.349, -1.4859)
  line L659 (31.381, 20.349, -1.4859) -> (31.2919, 20.5238, -1.4859)
  line L660 (31.2919, 20.5238, -1.4859) -> (31.2313, 20.7103, -1.4859)
  line L661 (31.2313, 20.7103, -1.4859) -> (31.2006, 20.904, -1.4859)
  line L662 (31.2006, 20.904, -1.4859) -> (31.1968, 21.0021, -1.4859)
  line L663 (31.1968, 21.0021, -1.4859) -> (31.1968, 21.5021, -1.4859)
  line L664 (31.1968, 21.5021, -1.4859) -> (31.2006, 21.6002, -1.4859)
  line L665 (31.2006, 21.6002, -1.4859) -> (31.2313, 21.7939, -1.4859)
  line L666 (31.2313, 21.7939, -1.4859) -> (31.2919, 21.9805, -1.4859)
  line L667 (31.2919, 21.9805, -1.4859) -> (31.381, 22.1552, -1.4859)
  line L668 (31.381, 22.1552, -1.4859) -> (31.4963, 22.3139, -1.4859)
  line L669 (31.4963, 22.3139, -1.4859) -> (31.635, 22.4526, -1.4859)
  line L670 (31.635, 22.4526, -1.4859) -> (31.7936, 22.5679, -1.4859)
  line L671 (31.7936, 22.5679, -1.4859) -> (31.9684, 22.657, -1.4859)
  line L672 (31.9684, 22.657, -1.4859) -> (32.155, 22.7176, -1.4859)
  line L673 (32.155, 22.7176, -1.4859) -> (32.3487, 22.7483, -1.4859)
  line L674 (32.3487, 22.7483, -1.4859) -> (32.5448, 22.7483, -1.4859)
  line L675 (32.5448, 22.7483, -1.4859) -> (32.7386, 22.7176, -1.4859)
  line L676 (93.6986, 22.7176, -1.4859) -> (93.8851, 22.657, -1.4859)
  line L677 (93.8851, 22.657, -1.4859) -> (94.0599, 22.5679, -1.4859)
  line L678 (94.0599, 22.5679, -1.4859) -> (94.2186, 22.4526, -1.4859)
  line L679 (94.2186, 22.4526, -1.4859) -> (94.3573, 22.3139, -1.4859)
  line L680 (94.3573, 22.3139, -1.4859) -> (94.4726, 22.1552, -1.4859)
  line L681 (94.4726, 22.1552, -1.4859) -> (94.5616, 21.9805, -1.4859)
  line L682 (94.5616, 21.9805, -1.4859) -> (94.6222, 21.7939, -1.4859)
  line L683 (94.6222, 21.7939, -1.4859) -> (94.6529, 21.6002, -1.4859)
  line L684 (94.6529, 21.6002, -1.4859) -> (94.6568, 21.5021, -1.4859)
  line L685 (94.6568, 21.5021, -1.4859) -> (94.6568, 21.0021, -1.4859)
  line L686 (94.6568, 21.0021, -1.4859) -> (94.6529, 20.904, -1.4859)
  line L687 (94.6529, 20.904, -1.4859) -> (94.6222, 20.7103, -1.4859)
  line L688 (94.6222, 20.7103, -1.4859) -> (94.5616, 20.5238, -1.4859)
  line L689 (94.5616, 20.5238, -1.4859) -> (94.4726, 20.349, -1.4859)
  line L690 (94.4726, 20.349, -1.4859) -> (94.3573, 20.1903, -1.4859)
  line L691 (94.3573, 20.1903, -1.4859) -> (94.2186, 20.0516, -1.4859)
  line L692 (94.2186, 20.0516, -1.4859) -> (94.0599, 19.9363, -1.4859)
  line L693 (94.0599, 19.9363, -1.4859) -> (93.8851, 19.8473, -1.4859)
  line L694 (93.8851, 19.8473, -1.4859) -> (93.6986, 19.7866, -1.4859)
  line L695 (93.6986, 19.7866, -1.4859) -> (93.5048, 19.756, -1.4859)
  line L696 (93.5048, 19.756, -1.4859) -> (93.3087, 19.756, -1.4859)
  line L697 (93.3087, 19.756, -1.4859) -> (93.115, 19.7866, -1.4859)
  line L698 (93.115, 19.7866, -1.4859) -> (92.9284, 19.8473, -1.4859)
  line L699 (92.9284, 19.8473, -1.4859) -> (92.7536, 19.9363, -1.4859)
  line L700 (92.7536, 19.9363, -1.4859) -> (92.595, 20.0516, -1.4859)
  line L701 (92.595, 20.0516, -1.4859) -> (92.4563, 20.1903, -1.4859)
  line L702 (92.4563, 20.1903, -1.4859) -> (92.341, 20.349, -1.4859)
  line L703 (92.341, 20.349, -1.4859) -> (92.2519, 20.5238, -1.4859)
  line L704 (92.2519, 20.5238, -1.4859) -> (92.1913, 20.7103, -1.4859)
  line L705 (92.1913, 20.7103, -1.4859) -> (92.1606, 20.904, -1.4859)
  line L706 (92.1606, 20.904, -1.4859) -> (92.1568, 21.0021, -1.4859)
  line L707 (92.1568, 21.0021, -1.4859) -> (92.1568, 21.5021, -1.4859)
  line L708 (92.1568, 21.5021, -1.4859) -> (92.1606, 21.6002, -1.4859)
  line L709 (92.1606, 21.6002, -1.4859) -> (92.1913, 21.7939, -1.4859)
  line L710 (92.1913, 21.7939, -1.4859) -> (92.2519, 21.9805, -1.4859)
  line L711 (92.2519, 21.9805, -1.4859) -> (92.341, 22.1552, -1.4859)
  line L712 (92.341, 22.1552, -1.4859) -> (92.4563, 22.3139, -1.4859)
  line L713 (92.4563, 22.3139, -1.4859) -> (92.595, 22.4526, -1.4859)
  line L714 (92.595, 22.4526, -1.4859) -> (92.7536, 22.5679, -1.4859)
  line L715 (92.7536, 22.5679, -1.4859) -> (92.9284, 22.657, -1.4859)
  line L716 (92.9284, 22.657, -1.4859) -> (93.115, 22.7176, -1.4859)
  line L717 (93.115, 22.7176, -1.4859) -> (93.3087, 22.7483, -1.4859)
  line L718 (93.3087, 22.7483, -1.4859) -> (93.5048, 22.7483, -1.4859)
  line L719 (93.5048, 22.7483, -1.4859) -> (93.6986, 22.7176, -1.4859)
  line L720 (44.7153, 20.1184, -1.4859) -> (41.5153, 20.1184, -1.4859)
  line L721 (41.5153, 20.1184, -1.4859) -> (41.5153, 22.1184, -1.4859)
  line L722 (41.5153, 22.1184, -1.4859) -> (44.7153, 22.1184, -1.4859)
  line L723 (44.7153, 22.1184, -1.4859) -> (44.7153, 20.1184, -1.4859)
  line L724 (105.6753, 20.1184, -1.4859) -> (102.4753, 20.1184, -1.4859)
  line L725 (102.4753, 20.1184, -1.4859) -> (102.4753, 22.1184, -1.4859)
  line L726 (102.4753, 22.1184, -1.4859) -> (105.6753, 22.1184, -1.4859)
  line L727 (105.6753, 22.1184, -1.4859) -> (105.6753, 20.1184, -1.4859)
  line L728 (60.3483, 20.3076, -1.4859) -> (57.3483, 20.3076, -1.4859)
  line L729 (57.3483, 20.3076, -1.4859) -> (57.3483, 22.7576, -1.4859)
  line L730 (57.3483, 22.7576, -1.4859) -> (60.3483, 22.7576, -1.4859)
  line L731 (60.3483, 22.7576, -1.4859) -> (60.3483, 20.3076, -1.4859)
  line L732 (121.3083, 20.3076, -1.4859) -> (118.3083, 20.3076, -1.4859)
  line L733 (118.3083, 20.3076, -1.4859) -> (118.3083, 22.7576, -1.4859)
  line L734 (118.3083, 22.7576, -1.4859) -> (121.3083, 22.7576, -1.4859)
  line L735 (121.3083, 22.7576, -1.4859) -> (121.3083, 20.3076, -1.4859)
  line L736 (50.1588, 24.7613, -1.4859) -> (50.3454, 24.7007, -1.4859)
  line L737 (50.3454, 24.7007, -1.4859) -> (50.5202, 24.6116, -1.4859)
  line L738 (50.5202, 24.6116, -1.4859) -> (50.6788, 24.4963, -1.4859)
  line L739 (50.6788, 24.4963, -1.4859) -> (50.8175, 24.3576, -1.4859)
  line L740 (50.8175, 24.3576, -1.4859) -> (50.9328, 24.1989, -1.4859)
  line L741 (50.9328, 24.1989, -1.4859) -> (51.0219, 24.0242, -1.4859)
  line L742 (51.0219, 24.0242, -1.4859) -> (51.0825, 23.8376, -1.4859)
  line L743 (51.0825, 23.8376, -1.4859) -> (51.1132, 23.6439, -1.4859)
  line L744 (51.1132, 23.6439, -1.4859) -> (51.117, 23.5458, -1.4859)
  line L745 (51.117, 23.5458, -1.4859) -> (51.117, 23.0458, -1.4859)
  line L746 (51.117, 23.0458, -1.4859) -> (51.1132, 22.9477, -1.4859)
  line L747 (51.1132, 22.9477, -1.4859) -> (51.0825, 22.754, -1.4859)
  line L748 (51.0825, 22.754, -1.4859) -> (51.0219, 22.5675, -1.4859)
  line L749 (51.0219, 22.5675, -1.4859) -> (50.9328, 22.3927, -1.4859)
  line L750 (50.9328, 22.3927, -1.4859) -> (50.8175, 22.234, -1.4859)
  line L751 (50.8175, 22.234, -1.4859) -> (50.6788, 22.0953, -1.4859)
  line L752 (50.6788, 22.0953, -1.4859) -> (50.5202, 21.98, -1.4859)
  line L753 (50.5202, 21.98, -1.4859) -> (50.3454, 21.891, -1.4859)
  line L754 (50.3454, 21.891, -1.4859) -> (50.1588, 21.8304, -1.4859)
  line L755 (50.1588, 21.8304, -1.4859) -> (49.9651, 21.7997, -1.4859)
  line L756 (49.9651, 21.7997, -1.4859) -> (49.769, 21.7997, -1.4859)
  line L757 (49.769, 21.7997, -1.4859) -> (49.5752, 21.8304, -1.4859)
  line L758 (49.5752, 21.8304, -1.4859) -> (49.3887, 21.891, -1.4859)
  line L759 (49.3887, 21.891, -1.4859) -> (49.2139, 21.98, -1.4859)
  line L760 (49.2139, 21.98, -1.4859) -> (49.0552, 22.0953, -1.4859)
  line L761 (49.0552, 22.0953, -1.4859) -> (48.9165, 22.234, -1.4859)
  line L762 (48.9165, 22.234, -1.4859) -> (48.8012, 22.3927, -1.4859)
  line L763 (48.8012, 22.3927, -1.4859) -> (48.7122, 22.5675, -1.4859)
  line L764 (48.7122, 22.5675, -1.4859) -> (48.6516, 22.754, -1.4859)
  line L765 (48.6516, 22.754, -1.4859) -> (48.6209, 22.9477, -1.4859)
  line L766 (48.6209, 22.9477, -1.4859) -> (48.617, 23.0458, -1.4859)
  line L767 (48.617, 23.0458, -1.4859) -> (48.617, 23.5458, -1.4859)
  line L768 (48.617, 23.5458, -1.4859) -> (48.6209, 23.6439, -1.4859)
  line L769 (48.6209, 23.6439, -1.4859) -> (48.6516, 23.8376, -1.4859)
  line L770 (48.6516, 23.8376, -1.4859) -> (48.7122, 24.0242, -1.4859)
  line L771 (48.7122, 24.0242, -1.4859) -> (48.8012, 24.1989, -1.4859)
  line L772 (48.8012, 24.1989, -1.4859) -> (48.9165, 24.3576, -1.4859)
  line L773 (48.9165, 24.3576, -1.4859) -> (49.0552, 24.4963, -1.4859)
  line L774 (49.0552, 24.4963, -1.4859) -> (49.2139, 24.6116, -1.4859)
  line L775 (49.2139, 24.6116, -1.4859) -> (49.3887, 24.7007, -1.4859)
  line L776 (49.3887, 24.7007, -1.4859) -> (49.5752, 24.7613, -1.4859)
  line L777 (49.5752, 24.7613, -1.4859) -> (49.769, 24.792, -1.4859)
  line L778 (49.769, 24.792, -1.4859) -> (49.9651, 24.792, -1.4859)
  line L779 (49.9651, 24.792, -1.4859) -> (50.1588, 24.7613, -1.4859)
  line L780 (111.1188, 24.7613, -1.4859) -> (111.3054, 24.7007, -1.4859)
  line L781 (111.3054, 24.7007, -1.4859) -> (111.4802, 24.6116, -1.4859)
  line L782 (111.4802, 24.6116, -1.4859) -> (111.6388, 24.4963, -1.4859)
  line L783 (111.6388, 24.4963, -1.4859) -> (111.7775, 24.3576, -1.4859)
  line L784 (111.7775, 24.3576, -1.4859) -> (111.8928, 24.1989, -1.4859)
  line L785 (111.8928, 24.1989, -1.4859) -> (111.9819, 24.0242, -1.4859)
  line L786 (111.9819, 24.0242, -1.4859) -> (112.0425, 23.8376, -1.4859)
  line L787 (112.0425, 23.8376, -1.4859) -> (112.0732, 23.6439, -1.4859)
  line L788 (112.0732, 23.6439, -1.4859) -> (112.077, 23.5458, -1.4859)
  line L789 (112.077, 23.5458, -1.4859) -> (112.077, 23.0458, -1.4859)
  line L790 (112.077, 23.0458, -1.4859) -> (112.0732, 22.9477, -1.4859)
  line L791 (112.0732, 22.9477, -1.4859) -> (112.0425, 22.754, -1.4859)
  line L792 (112.0425, 22.754, -1.4859) -> (111.9819, 22.5675, -1.4859)
  line L793 (111.9819, 22.5675, -1.4859) -> (111.8928, 22.3927, -1.4859)
  line L794 (111.8928, 22.3927, -1.4859) -> (111.7775, 22.234, -1.4859)
  line L795 (111.7775, 22.234, -1.4859) -> (111.6388, 22.0953, -1.4859)
  line L796 (111.6388, 22.0953, -1.4859) -> (111.4802, 21.98, -1.4859)
  line L797 (111.4802, 21.98, -1.4859) -> (111.3054, 21.891, -1.4859)
  line L798 (111.3054, 21.891, -1.4859) -> (111.1188, 21.8304, -1.4859)
  line L799 (111.1188, 21.8304, -1.4859) -> (110.9251, 21.7997, -1.4859)
  line L800 (110.9251, 21.7997, -1.4859) -> (110.729, 21.7997, -1.4859)
  line L801 (110.729, 21.7997, -1.4859) -> (110.5352, 21.8304, -1.4859)
  line L802 (110.5352, 21.8304, -1.4859) -> (110.3487, 21.891, -1.4859)
  line L803 (110.3487, 21.891, -1.4859) -> (110.1739, 21.98, -1.4859)
  line L804 (110.1739, 21.98, -1.4859) -> (110.0152, 22.0953, -1.4859)
  line L805 (110.0152, 22.0953, -1.4859) -> (109.8765, 22.234, -1.4859)
  line L806 (109.8765, 22.234, -1.4859) -> (109.7612, 22.3927, -1.4859)
  line L807 (109.7612, 22.3927, -1.4859) -> (109.6722, 22.5675, -1.4859)
  line L808 (109.6722, 22.5675, -1.4859) -> (109.6116, 22.754, -1.4859)
  line L809 (109.6116, 22.754, -1.4859) -> (109.5809, 22.9477, -1.4859)
  line L810 (109.5809, 22.9477, -1.4859) -> (109.577, 23.0458, -1.4859)
  line L811 (109.577, 23.0458, -1.4859) -> (109.577, 23.5458, -1.4859)
  line L812 (109.577, 23.5458, -1.4859) -> (109.5809, 23.6439, -1.4859)
  line L813 (109.5809, 23.6439, -1.4859) -> (109.6116, 23.8376, -1.4859)
  line L814 (109.6116, 23.8376, -1.4859) -> (109.6722, 24.0242, -1.4859)
  line L815 (109.6722, 24.0242, -1.4859) -> (109.7612, 24.1989, -1.4859)
  line L816 (109.7612, 24.1989, -1.4859) -> (109.8765, 24.3576, -1.4859)
  line L817 (109.8765, 24.3576, -1.4859) -> (110.0152, 24.4963, -1.4859)
  line L818 (110.0152, 24.4963, -1.4859) -> (110.1739, 24.6116, -1.4859)
  line L819 (110.1739, 24.6116, -1.4859) -> (110.3487, 24.7007, -1.4859)
  line L820 (110.3487, 24.7007, -1.4859) -> (110.5352, 24.7613, -1.4859)
  line L821 (110.5352, 24.7613, -1.4859) -> (110.729, 24.792, -1.4859)
  line L822 (110.729, 24.792, -1.4859) -> (110.9251, 24.792, -1.4859)
  line L823 (110.9251, 24.792, -1.4859) -> (111.1188, 24.7613, -1.4859)
  line L824 (59.2194, 25.2939, -1.4859) -> (59.4093, 25.2638, -1.4859)
  line L825 (59.4093, 25.2638, -1.4859) -> (59.5921, 25.2044, -1.4859)
  line L826 (59.5921, 25.2044, -1.4859) -> (59.7634, 25.1171, -1.4859)
  line L827 (59.7634, 25.1171, -1.4859) -> (59.9189, 25.0041, -1.4859)
  line L828 (59.9189, 25.0041, -1.4859) -> (60.0548, 24.8682, -1.4859)
  line L829 (60.0548, 24.8682, -1.4859) -> (60.1678, 24.7127, -1.4859)
  line L830 (60.1678, 24.7127, -1.4859) -> (60.2551, 24.5414, -1.4859)
  line L831 (60.2551, 24.5414, -1.4859) -> (60.3145, 24.3586, -1.4859)
  line L832 (60.3145, 24.3586, -1.4859) -> (60.3445, 24.1687, -1.4859)
  line L833 (60.3445, 24.1687, -1.4859) -> (60.3445, 23.9765, -1.4859)
  line L834 (60.3445, 23.9765, -1.4859) -> (60.3145, 23.7867, -1.4859)
  line L835 (60.3145, 23.7867, -1.4859) -> (60.2551, 23.6038, -1.4859)
  line L836 (60.2551, 23.6038, -1.4859) -> (60.1678, 23.4326, -1.4859)
  line L837 (60.1678, 23.4326, -1.4859) -> (60.0548, 23.2771, -1.4859)
  line L838 (60.0548, 23.2771, -1.4859) -> (59.9189, 23.1411, -1.4859)
  line L839 (59.9189, 23.1411, -1.4859) -> (59.7634, 23.0281, -1.4859)
  line L840 (59.7634, 23.0281, -1.4859) -> (59.5921, 22.9409, -1.4859)
  line L841 (59.5921, 22.9409, -1.4859) -> (59.4093, 22.8815, -1.4859)
  line L842 (59.4093, 22.8815, -1.4859) -> (59.2194, 22.8514, -1.4859)
  line L843 (59.2194, 22.8514, -1.4859) -> (59.1233, 22.8476, -1.4859)
  line L844 (59.1233, 22.8476, -1.4859) -> (58.5733, 22.8476, -1.4859)
  line L845 (58.5733, 22.8476, -1.4859) -> (58.4772, 22.8514, -1.4859)
  line L846 (58.4772, 22.8514, -1.4859) -> (58.2873, 22.8815, -1.4859)
  line L847 (58.2873, 22.8815, -1.4859) -> (58.1045, 22.9409, -1.4859)
  line L848 (58.1045, 22.9409, -1.4859) -> (57.9333, 23.0281, -1.4859)
  line L849 (57.9333, 23.0281, -1.4859) -> (57.7777, 23.1411, -1.4859)
  line L850 (57.7777, 23.1411, -1.4859) -> (57.6418, 23.2771, -1.4859)
  line L851 (57.6418, 23.2771, -1.4859) -> (57.5288, 23.4326, -1.4859)
  line L852 (57.5288, 23.4326, -1.4859) -> (57.4416, 23.6038, -1.4859)
  line L853 (57.4416, 23.6038, -1.4859) -> (57.3822, 23.7867, -1.4859)
  line L854 (57.3822, 23.7867, -1.4859) -> (57.3521, 23.9765, -1.4859)
  line L855 (57.3521, 23.9765, -1.4859) -> (57.3521, 24.1687, -1.4859)
  line L856 (57.3521, 24.1687, -1.4859) -> (57.3822, 24.3586, -1.4859)
  line L857 (57.3822, 24.3586, -1.4859) -> (57.4416, 24.5414, -1.4859)
  line L858 (57.4416, 24.5414, -1.4859) -> (57.5288, 24.7127, -1.4859)
  line L859 (57.5288, 24.7127, -1.4859) -> (57.6418, 24.8682, -1.4859)
  line L860 (57.6418, 24.8682, -1.4859) -> (57.7777, 25.0041, -1.4859)
  line L861 (57.7777, 25.0041, -1.4859) -> (57.9333, 25.1171, -1.4859)
  line L862 (57.9333, 25.1171, -1.4859) -> (58.1045, 25.2044, -1.4859)
  line L863 (58.1045, 25.2044, -1.4859) -> (58.2873, 25.2638, -1.4859)
  line L864 (58.2873, 25.2638, -1.4859) -> (58.4772, 25.2939, -1.4859)
  line L865 (58.4772, 25.2939, -1.4859) -> (58.5733, 25.2976, -1.4859)
  line L866 (58.5733, 25.2976, -1.4859) -> (59.1233, 25.2976, -1.4859)
  line L867 (59.1233, 25.2976, -1.4859) -> (59.2194, 25.2939, -1.4859)
  line L868 (120.1794, 25.2939, -1.4859) -> (120.3693, 25.2638, -1.4859)
  line L869 (120.3693, 25.2638, -1.4859) -> (120.5521, 25.2044, -1.4859)
  line L870 (120.5521, 25.2044, -1.4859) -> (120.7234, 25.1171, -1.4859)
  line L871 (120.7234, 25.1171, -1.4859) -> (120.8789, 25.0041, -1.4859)
  line L872 (120.8789, 25.0041, -1.4859) -> (121.0148, 24.8682, -1.4859)
  line L873 (121.0148, 24.8682, -1.4859) -> (121.1278, 24.7127, -1.4859)
  line L874 (121.1278, 24.7127, -1.4859) -> (121.2151, 24.5414, -1.4859)
  line L875 (121.2151, 24.5414, -1.4859) -> (121.2745, 24.3586, -1.4859)
  line L876 (121.2745, 24.3586, -1.4859) -> (121.3045, 24.1687, -1.4859)
  line L877 (121.3045, 24.1687, -1.4859) -> (121.3045, 23.9765, -1.4859)
  line L878 (121.3045, 23.9765, -1.4859) -> (121.2745, 23.7867, -1.4859)
  line L879 (121.2745, 23.7867, -1.4859) -> (121.2151, 23.6038, -1.4859)
  line L880 (121.2151, 23.6038, -1.4859) -> (121.1278, 23.4326, -1.4859)
  line L881 (121.1278, 23.4326, -1.4859) -> (121.0148, 23.2771, -1.4859)
  line L882 (121.0148, 23.2771, -1.4859) -> (120.8789, 23.1411, -1.4859)
  line L883 (120.8789, 23.1411, -1.4859) -> (120.7234, 23.0281, -1.4859)
  line L884 (120.7234, 23.0281, -1.4859) -> (120.5521, 22.9409, -1.4859)
  line L885 (120.5521, 22.9409, -1.4859) -> (120.3693, 22.8815, -1.4859)
  line L886 (120.3693, 22.8815, -1.4859) -> (120.1794, 22.8514, -1.4859)
  line L887 (120.1794, 22.8514, -1.4859) -> (120.0833, 22.8476, -1.4859)
  line L888 (120.0833, 22.8476, -1.4859) -> (119.5333, 22.8476, -1.4859)
  line L889 (119.5333, 22.8476, -1.4859) -> (119.4372, 22.8514, -1.4859)
  line L890 (119.4372, 22.8514, -1.4859) -> (119.2473, 22.8815, -1.4859)
  line L891 (119.2473, 22.8815, -1.4859) -> (119.0645, 22.9409, -1.4859)
  line L892 (119.0645, 22.9409, -1.4859) -> (118.8933, 23.0281, -1.4859)
  line L893 (118.8933, 23.0281, -1.4859) -> (118.7377, 23.1411, -1.4859)
  line L894 (118.7377, 23.1411, -1.4859) -> (118.6018, 23.2771, -1.4859)
  line L895 (118.6018, 23.2771, -1.4859) -> (118.4888, 23.4326, -1.4859)
  line L896 (118.4888, 23.4326, -1.4859) -> (118.4016, 23.6038, -1.4859)
  line L897 (118.4016, 23.6038, -1.4859) -> (118.3422, 23.7867, -1.4859)
  line L898 (118.3422, 23.7867, -1.4859) -> (118.3121, 23.9765, -1.4859)
  line L899 (118.3121, 23.9765, -1.4859) -> (118.3121, 24.1687, -1.4859)
  line L900 (118.3121, 24.1687, -1.4859) -> (118.3422, 24.3586, -1.4859)
  line L901 (118.3422, 24.3586, -1.4859) -> (118.4016, 24.5414, -1.4859)
  line L902 (118.4016, 24.5414, -1.4859) -> (118.4888, 24.7127, -1.4859)
  line L903 (118.4888, 24.7127, -1.4859) -> (118.6018, 24.8682, -1.4859)
  line L904 (118.6018, 24.8682, -1.4859) -> (118.7377, 25.0041, -1.4859)
  line L905 (118.7377, 25.0041, -1.4859) -> (118.8933, 25.1171, -1.4859)
  line L906 (118.8933, 25.1171, -1.4859) -> (119.0645, 25.2044, -1.4859)
  line L907 (119.0645, 25.2044, -1.4859) -> (119.2473, 25.2638, -1.4859)
  line L908 (119.2473, 25.2638, -1.4859) -> (119.4372, 25.2939, -1.4859)
  line L909 (119.4372, 25.2939, -1.4859) -> (119.5333, 25.2976, -1.4859)
  line L910 (119.5333, 25.2976, -1.4859) -> (120.0833, 25.2976, -1.4859)
  line L911 (120.0833, 25.2976, -1.4859) -> (120.1794, 25.2939, -1.4859)
  line L912 (43.8715, 27.1487, -1.4859) -> (44.0638, 27.1104, -1.4859)
  line L913 (44.0638, 27.1104, -1.4859) -> (44.2449, 27.0354, -1.4859)
  line L914 (44.2449, 27.0354, -1.4859) -> (44.4079, 26.9265, -1.4859)
  line L915 (44.4079, 26.9265, -1.4859) -> (44.5465, 26.7879, -1.4859)
  line L916 (44.5465, 26.7879, -1.4859) -> (44.6554, 26.6249, -1.4859)
  line L917 (44.6554, 26.6249, -1.4859) -> (44.7304, 26.4438, -1.4859)
  line L918 (44.7304, 26.4438, -1.4859) -> (44.7687, 26.2515, -1.4859)
  line L919 (44.7687, 26.2515, -1.4859) -> (44.7687, 26.0555, -1.4859)
  line L920 (44.7687, 26.0555, -1.4859) -> (44.7304, 25.8632, -1.4859)
  line L921 (44.7304, 25.8632, -1.4859) -> (44.6554, 25.6821, -1.4859)
  line L922 (44.6554, 25.6821, -1.4859) -> (44.5465, 25.5191, -1.4859)
  line L923 (44.5465, 25.5191, -1.4859) -> (44.4079, 25.3805, -1.4859)
  line L924 (44.4079, 25.3805, -1.4859) -> (44.2449, 25.2716, -1.4859)
  line L925 (44.2449, 25.2716, -1.4859) -> (44.0638, 25.1965, -1.4859)
  line L926 (44.0638, 25.1965, -1.4859) -> (43.8715, 25.1583, -1.4859)
  line L927 (43.8715, 25.1583, -1.4859) -> (43.7735, 25.1535, -1.4859)
  line L928 (43.7735, 25.1535, -1.4859) -> (42.5735, 25.1535, -1.4859)
  line L929 (42.5735, 25.1535, -1.4859) -> (42.4755, 25.1583, -1.4859)
  line L930 (42.4755, 25.1583, -1.4859) -> (42.2832, 25.1965, -1.4859)
  line L931 (42.2832, 25.1965, -1.4859) -> (42.1021, 25.2716, -1.4859)
  line L932 (42.1021, 25.2716, -1.4859) -> (41.9391, 25.3805, -1.4859)
  line L933 (41.9391, 25.3805, -1.4859) -> (41.8005, 25.5191, -1.4859)
  line L934 (41.8005, 25.5191, -1.4859) -> (41.6916, 25.6821, -1.4859)
  line L935 (41.6916, 25.6821, -1.4859) -> (41.6165, 25.8632, -1.4859)
  line L936 (41.6165, 25.8632, -1.4859) -> (41.5783, 26.0555, -1.4859)
  line L937 (41.5783, 26.0555, -1.4859) -> (41.5783, 26.2515, -1.4859)
  line L938 (41.5783, 26.2515, -1.4859) -> (41.6165, 26.4438, -1.4859)
  line L939 (41.6165, 26.4438, -1.4859) -> (41.6916, 26.6249, -1.4859)
  line L940 (41.6916, 26.6249, -1.4859) -> (41.8005, 26.7879, -1.4859)
  line L941 (41.8005, 26.7879, -1.4859) -> (41.9391, 26.9265, -1.4859)
  line L942 (41.9391, 26.9265, -1.4859) -> (42.1021, 27.0354, -1.4859)
  line L943 (42.1021, 27.0354, -1.4859) -> (42.2832, 27.1104, -1.4859)
  line L944 (42.2832, 27.1104, -1.4859) -> (42.4755, 27.1487, -1.4859)
  line L945 (42.4755, 27.1487, -1.4859) -> (42.5735, 27.1535, -1.4859)
  line L946 (42.5735, 27.1535, -1.4859) -> (43.7735, 27.1535, -1.4859)
  line L947 (43.7735, 27.1535, -1.4859) -> (43.8715, 27.1487, -1.4859)
  line L948 (104.8315, 27.1487, -1.4859) -> (105.0238, 27.1104, -1.4859)
  line L949 (105.0238, 27.1104, -1.4859) -> (105.2049, 27.0354, -1.4859)
  line L950 (105.2049, 27.0354, -1.4859) -> (105.3679, 26.9265, -1.4859)
  line L951 (105.3679, 26.9265, -1.4859) -> (105.5065, 26.7879, -1.4859)
  line L952 (105.5065, 26.7879, -1.4859) -> (105.6154, 26.6249, -1.4859)
  line L953 (105.6154, 26.6249, -1.4859) -> (105.6904, 26.4438, -1.4859)
  line L954 (105.6904, 26.4438, -1.4859) -> (105.7287, 26.2515, -1.4859)
  line L955 (105.7287, 26.2515, -1.4859) -> (105.7287, 26.0555, -1.4859)
  line L956 (105.7287, 26.0555, -1.4859) -> (105.6904, 25.8632, -1.4859)
  line L957 (105.6904, 25.8632, -1.4859) -> (105.6154, 25.6821, -1.4859)
  line L958 (105.6154, 25.6821, -1.4859) -> (105.5065, 25.5191, -1.4859)
  line L959 (105.5065, 25.5191, -1.4859) -> (105.3679, 25.3805, -1.4859)
  line L960 (105.3679, 25.3805, -1.4859) -> (105.2049, 25.2716, -1.4859)
  line L961 (105.2049, 25.2716, -1.4859) -> (105.0238, 25.1965, -1.4859)
  line L962 (105.0238, 25.1965, -1.4859) -> (104.8315, 25.1583, -1.4859)
  line L963 (104.8315, 25.1583, -1.4859) -> (104.7335, 25.1535, -1.4859)
  line L964 (104.7335, 25.1535, -1.4859) -> (103.5335, 25.1535, -1.4859)
  line L965 (103.5335, 25.1535, -1.4859) -> (103.4355, 25.1583, -1.4859)
  line L966 (103.4355, 25.1583, -1.4859) -> (103.2432, 25.1965, -1.4859)
  line L967 (103.2432, 25.1965, -1.4859) -> (103.0621, 25.2716, -1.4859)
  line L968 (103.0621, 25.2716, -1.4859) -> (102.8991, 25.3805, -1.4859)
  line L969 (102.8991, 25.3805, -1.4859) -> (102.7605, 25.5191, -1.4859)
  line L970 (102.7605, 25.5191, -1.4859) -> (102.6516, 25.6821, -1.4859)
  line L971 (102.6516, 25.6821, -1.4859) -> (102.5765, 25.8632, -1.4859)
  line L972 (102.5765, 25.8632, -1.4859) -> (102.5383, 26.0555, -1.4859)
  line L973 (102.5383, 26.0555, -1.4859) -> (102.5383, 26.2515, -1.4859)
  line L974 (102.5383, 26.2515, -1.4859) -> (102.5765, 26.4438, -1.4859)
  line L975 (102.5765, 26.4438, -1.4859) -> (102.6516, 26.6249, -1.4859)
  line L976 (102.6516, 26.6249, -1.4859) -> (102.7605, 26.7879, -1.4859)
  line L977 (102.7605, 26.7879, -1.4859) -> (102.8991, 26.9265, -1.4859)
  line L978 (102.8991, 26.9265, -1.4859) -> (103.0621, 27.0354, -1.4859)
  line L979 (103.0621, 27.0354, -1.4859) -> (103.2432, 27.1104, -1.4859)
  line L980 (103.2432, 27.1104, -1.4859) -> (103.4355, 27.1487, -1.4859)
  line L981 (103.4355, 27.1487, -1.4859) -> (103.5335, 27.1535, -1.4859)
  line L982 (103.5335, 27.1535, -1.4859) -> (104.7335, 27.1535, -1.4859)
  line L983 (104.7335, 27.1535, -1.4859) -> (104.8315, 27.1487, -1.4859)
  line L984 (32.7386, 30.3376, -1.4859) -> (32.9251, 30.277, -1.4859)